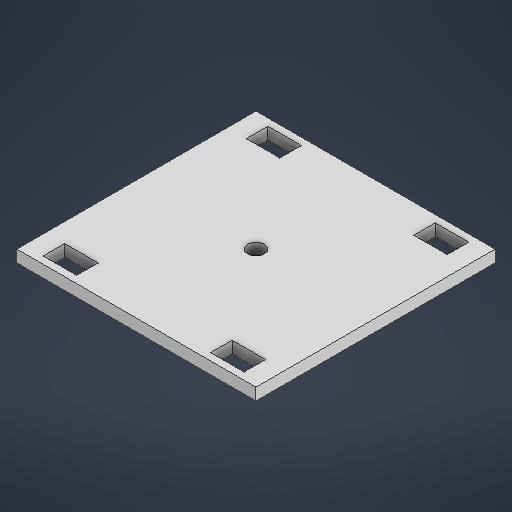
# Autodesk Inventor part: Medio
Saved by Autodesk Inventor 2025.2 (Build 292293000, 293)
## iProperties
Created: 2025-06-04
Part Number: Medio
Material: Genérico
Document SubType Name: Modeling
Designer: Niko
Density: 1 g/cm^3
Appearance: Valor por defecto
Author: Niko
Autodesk Inventor part; units mm, degrees
ref_plane "YZ Plane" through (0, 0, 0) normal (1, 0, 0) x (0, 1, 0)
ref_plane "XZ Plane" through (0, 0, 0) normal (0, 1, 0) x (-1, 0, 0)
ref_plane "XY Plane" through (0, 0, 0) normal (0, 0, 1) x (1, 0, 0)
sketch "Boceto1" plane through (0, 0, 0) normal (0, 1, 0) x (-1, 0, 0)
  line L0 (50, 50) -> (-50, 50)
  line L1 (-50, 50) -> (-50, -50)
  line L2 (-50, -50) -> (50, -50)
  line L3 (50, -50) -> (50, 50)
  line L4 (50, 30) -> (50, 50)
  line L5 (50, 50) -> (50, 45)
  circle A0 centre (0, 0) radius 3.5
  line L6 (42, -45) -> (42, -47)
  line L7 (42, -47) -> (28, -47)
  line L8 (28, -47) -> (28, -38)
  line L9 (28, -38) -> (42, -38)
  line L10 (42, -38) -> (42, -47)
  line L11 (-42, -47) -> (-28, -47)
  line L12 (-28, -47) -> (-28, -38)
  line L13 (-28, -38) -> (-42, -38)
  line L14 (-42, -38) -> (-42, -47)
  line L15 (42, 45) -> (42, 47)
  line L16 (42, 47) -> (28, 47)
  line L17 (28, 47) -> (28, 38)
  line L18 (28, 38) -> (42, 38)
  line L19 (42, 38) -> (42, 47)
  line L20 (-28, 47) -> (-28, 38)
  line L21 (-42, 47) -> (-28, 47)
  line L22 (-42, 38) -> (-42, 47)
  line L23 (-28, 38) -> (-42, 38)
  constraints: 48 end point, 4 parallel, 2 horizontal, 2 perpendicular, 1 centre point, 1 point on line
extrude "Extrusión3" add sketch "Boceto1" along normal blind 5
